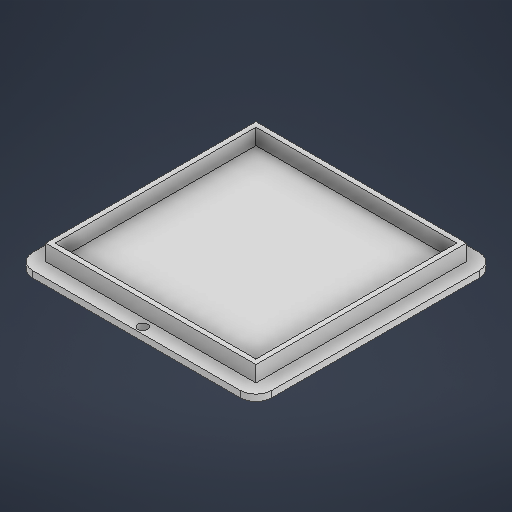
# Autodesk Inventor part: tampa
Saved by Autodesk Inventor 2026.2 (Build 302298010, 298A)
## iProperties
Created: 2026-08-15
Part Number: tampa
Material: Genérico
Document SubType Name: Sheet Metal
Designer: Admin
Density: 1 g/cm^3
Sheet Metal Rule: Padrão_mm
Appearance: Padrão
Author: Admin
## iProperties of the stored document tampa_3DPrint.ipt
Created: 2026-08-15
Part Number: tampa_3DPrint
Material: Genérico
Document SubType Name: Modeling
Designer: Admin
Density: 1 g/cm^3
Appearance: Padrão
Author: Admin
Autodesk Inventor part; units mm, degrees
ref_plane "YZ Plane" through (0, 0, 0) normal (1, 0, 0) x (0, 1, 0)
ref_plane "XZ Plane" through (0, 0, 0) normal (0, 1, 0) x (-1, 0, 0)
ref_plane "XY Plane" through (0, 0, 0) normal (0, 0, 1) x (1, 0, 0)
sketch "Esboço9" plane through (0, 0, 0) normal (0, 1, 0) x (-1, 0, 0)
  line L0 (5, 0) -> (70, 0)
  line L1 (75, -5) -> (75, -70)
  line L2 (70, -75) -> (5, -75)
  line L3 (0, -70) -> (0, -5)
  arc A0 (70, -75) -> (75, -70) centre (70, -70) ccw
  arc A1 (0, -70) -> (5, -75) centre (5, -70) ccw
  arc A2 (5, 0) -> (0, -5) centre (5, -5) ccw
  arc A3 (75, -5) -> (70, 0) centre (70, -5) ccw
  point P0 (0, 0)
  point P1 (75, -75)
  point P2 (75, 0)
  point P3 (0, -75)
  dimension "d46" = 75
  dimension "d47" = 75
  dimension "d48" = 5
  constraints: 8 end point, 8 point on circle, 8 point on line, 8 tangent, 4 centre point, 3 equal radius, 2 parallel, 1 horizontal, 1 perpendicular
  measures "d46" distance of point (75, -75) point (0, -75)
  measures "d47" distance of point (75, 0) point (75, -75)
  measures "d48" radius of A0
extrude "Extrusão7" add sketch "Esboço9" along normal blind 2
sketch "Esboço10" plane through (0, 2, 0) normal (0, 1, 0) x (1, 0, 0)
  arc A0 (-75, 5) -> (-70, 0) centre (-70, 5) ccw projected
  arc A1 (0, 70) -> (-5, 75) centre (-5, 70) ccw projected
  line L0 (-70, 5) -> (-5, 5)
  line L1 (-5, 5) -> (-5, 70)
  line L2 (-5, 70) -> (-70, 70)
  line L3 (-70, 70) -> (-70, 5)
  arc A2 (-70, 75) -> (-75, 70) centre (-70, 70) ccw projected
  line L4 (-75, 70) -> (-71, 70)
  line L5 (-75, 75) -> (-71, 75)
  line L6 (-71, 75) -> (-71, 71)
  line L7 (-71, 71) -> (-75, 71)
  line L8 (-75, 71) -> (-75, 75)
  line L9 (0, 75) -> (-4, 75)
  line L10 (-4, 75) -> (-4, 71)
  line L11 (-4, 71) -> (0, 71)
  line L12 (0, 71) -> (0, 75)
  line L13 (0, 0) -> (-4, 0)
  line L14 (-4, 0) -> (-4, 4)
  line L15 (-4, 4) -> (0, 4)
  line L16 (0, 4) -> (0, 0)
  line L17 (-75, 0) -> (-71, 0)
  line L18 (-71, 0) -> (-71, 4)
  line L19 (-71, 4) -> (-75, 4)
  line L20 (-75, 4) -> (-75, 0)
  line L21 (-71, 71) -> (-4, 71)
  line L22 (-4, 71) -> (-4, 4)
  line L23 (-4, 4) -> (-71, 4)
  line L24 (-71, 4) -> (-71, 71)
  line L25 (-71, 71) -> (-70.5, 71)
  line L26 (-70.5, 71) -> (-70.5, 70.5)
  line L27 (-70.5, 70.5) -> (-71, 70.5)
  line L28 (-71, 70.5) -> (-71, 71)
  line L29 (-4, 4) -> (-4.5, 4)
  line L30 (-4.5, 4) -> (-4.5, 4.5)
  line L31 (-4.5, 4.5) -> (-4, 4.5)
  line L32 (-4, 4.5) -> (-4, 4)
  line L33 (-70.5, 70.5) -> (-4.5, 70.5)
  line L34 (-4.5, 70.5) -> (-4.5, 4.5)
  line L35 (-4.5, 4.5) -> (-70.5, 4.5)
  line L36 (-70.5, 4.5) -> (-70.5, 70.5)
  line L37 (-70, 70) -> (-69, 70)
  line L38 (-69, 70) -> (-69, 69)
  line L39 (-69, 69) -> (-70, 69)
  line L40 (-70, 69) -> (-70, 70)
  line L41 (-5, 5) -> (-6, 5)
  line L42 (-6, 5) -> (-6, 6)
  line L43 (-6, 6) -> (-5, 6)
  line L44 (-5, 6) -> (-5, 5)
  line L45 (-69, 69) -> (-6, 69)
  line L46 (-6, 69) -> (-6, 6)
  line L47 (-6, 6) -> (-69, 6)
  line L48 (-69, 6) -> (-69, 69)
  dimension "d51" = 4
  dimension "d52" = 4
  dimension "d53" = 4
  dimension "d54" = 4
  dimension "d55" = 4
  dimension "d56" = 4
  dimension "d57" = 4
  dimension "d58" = 4
  dimension "d59" = 0.5
  dimension "d60" = 0.5
  dimension "d61" = 0.5
  dimension "d62" = 0.5
  dimension "d65" = 1
  dimension "d66" = 1
  dimension "d67" = 1
  dimension "d68" = 1
  constraints: 98 end point, 24 parallel, 13 horizontal, 12 perpendicular
  measures "d51" distance of L4.start L4.end
  measures "d52" distance of L5.end L6.end
  measures "d53" distance of L11.end L10.end
  measures "d54" distance of L10.end L9.end
  measures "d55" distance of L14.end L15.end
  measures "d56" distance of L13.end L14.end
  measures "d57" distance of L19.end L18.end
  measures "d58" distance of L18.end L17.end
  measures "d59" distance of L26.end L27.end
  measures "d60" distance of L25.end L26.end
  measures "d61" distance of L30.end L31.end
  measures "d62" distance of L29.end L30.end
  measures "d65" distance of L38.end L39.end
  measures "d66" distance of L37.end L38.end
  measures "d67" distance of L42.end L43.end
  measures "d68" distance of L41.end L42.end
extrude "Extrusão8" add sketch "Esboço10" along normal blind 5 contours L35 L36 L33 L34 | L3 L39 L48 L47 L42 L0 | L42 L43 L1 L0 | L3 L2 L38 L39 | L46 L45 L38 L2 L1 L43
sketch "Esboço11" plane through (0, 2, 0) normal (0, 1, 0) x (1, 0, 0)
  line L0 (-5, 75) -> (-70, 75) projected
  line L1 (-37.5, 75) -> (-37.5, 70.5)
  line L2 (-4.5, 70.5) -> (-70.5, 70.5) projected
  line L3 (-4.5, 4.5) -> (-70.5, 4.5) projected
  line L4 (-37.5, 4.5) -> (-37.5, 0)
  line L5 (-37.5, 75) -> (-37.5, 73)
  line L6 (-37.5, 0) -> (-37.5, 2)
  circle A0 centre (-37.5, 73) radius 1.5
  circle A1 centre (-37.5, 2) radius 1.5
  point P0 (0, 0)
  dimension "d69" = 2
  dimension "d70" = 2
  dimension "d71" = 3
  dimension "d72" = 3
  constraints: 8 end point, 3 midpoint, 3 point on line, 2 centre point, 2 coincident
  measures "d69" distance of L1.start L5.end
  measures "d70" distance of L4.end L6.end
  measures "d71" diameter of A0
  measures "d72" diameter of A1
extrude "Extrusão9" cut sketch "Esboço11" against normal through all
equation "\"Raio_vergadura\" = Espessura"
equation "\"Largura_alívio_de_vergadura\" = Espessura"
equation "\"Profundidade_alívio_de_vergadura\" = 0.5 * Espessura"
equation "\"Tamanho_alívio_de_dobra\" = 4 * Espessura"
equation "\"Remanescente_mínimo\" = 2 * Espessura"
equation "\"Raiodetransição\" = Raio_vergadura"
equation "\"Tamanho_de_raio_de_Jacobi\" = Raio_vergadura"
equation "\"TamanhoFolga\" = Espessura"
equation "\"Espessura\" = 0.5"
